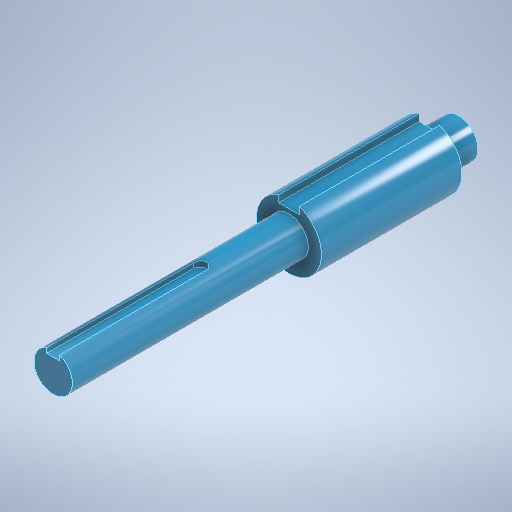
# Autodesk Inventor part: Output Shaft
Saved by Autodesk Inventor 2025 (Build 290162000, 162)
## iProperties
Created: 2024-05-11
Part Number: Output Shaft
Material: Generic
Document SubType Name: Modeling
Designer: BenFr
Density: 1 g/cm^3
Appearance: Sky Blue Dark
Author: BenFr
Autodesk Inventor part; units mm, degrees
ref_plane "YZ Plane" through (0, 0, 0) normal (1, 0, 0) x (0, 1, 0)
ref_plane "XZ Plane" through (0, 0, 0) normal (0, 1, 0) x (-1, 0, 0)
ref_plane "XY Plane" through (0, 0, 0) normal (0, 0, 1) x (1, 0, 0)
sketch "Sketch1" plane through (0, 0, 0) normal (0, 1, 0) x (-1, 0, 0)
  line L0 (0, 0) -> (0, -159.1)
  line L1 (0, 0) -> (7.5, 0)
  line L2 (7.5, 0) -> (7.5, -92.5)
  line L3 (7.5, -92.5) -> (12.7, -92.5)
  line L4 (12.7, -92.5) -> (12.7, -147.6)
  line L5 (12.7, -147.6) -> (7.5, -147.6)
  line L6 (7.5, -147.6) -> (7.5, -159.1)
  line L7 (7.5, -159.1) -> (0, -159.1)
  dimension "d0" = 159.1
  dimension "d1" = 7.5
  dimension "d2" = 92.5
  dimension "d3" = 5.2
  dimension "d4" = 55.1
  constraints: 16 end point, 5 perpendicular, 2 horizontal, 1 vertical
  measures "d0" distance of L0.start L0.end
  measures "d1" distance of L0.start L1.end
  measures "d2" distance of L1.end L2.end
  measures "d3" distance of L2.end L3.end
  measures "d4" distance of L3.end L4.end
revolve "Revolution1" add sketch "Sketch1" angle 360 about axis through (0, 0, 0) along (0, 0, -1)
sketch "Sketch2" plane through (0, 0, 0) normal (0, 0, 1) x (1, 0, 0)
  line L0 (-2.5, 5.15) -> (2.5, 5.15)
  line L1 (2.5, 5.15) -> (2.5, 9.85)
  line L2 (2.5, 9.85) -> (-2.5, 9.85)
  line L3 (-2.5, 9.85) -> (-2.5, 5.15)
  circle A0 centre (0, 0) radius 7.5 projected
  line L4 (-2.5, 5.15) -> (2.5, 9.85) construction
  line L5 (2.5, 5.15) -> (-2.5, 9.85) construction
  line L6 (4, 16.1) -> (-4, 16.1)
  line L7 (-4, 16.1) -> (-4, 9.3)
  line L8 (-4, 9.3) -> (4, 9.3)
  line L9 (4, 9.3) -> (4, 16.1)
  circle A1 centre (0, 0) radius 12.7 projected
  line L10 (4, 16.1) -> (-4, 9.3) construction
  line L11 (-4, 16.1) -> (4, 9.3) construction
  point P0 (0, 7.5)
  point P1 (0, 12.7)
  dimension "d6" = 5
  dimension "d7" = 4.7
  dimension "d8" = 8
  dimension "d9" = 6.8
  constraints: 24 end point, 4 midpoint, 4 parallel, 2 horizontal, 2 perpendicular, 2 vertical alignment, 2 other
  measures "d6" distance of L2.end L1.end
  measures "d7" distance of L1.end L0.end
  measures "d8" distance of L8.end L7.end
  measures "d9" distance of L7.end L6.end
extrude "Extrusion1" cut sketch "Sketch2" against normal blind 60 contours L3 A0 L1 L0 | L3 L8 L1 A0 | L3 L2 L1 L8 picked at (-0.2826, 5.9173)
sketch "Sketch3" plane through (0, 0, -92.5) normal (0, 0, 1) x (1, 0, 0)
  line L0 (-4, 9.3) -> (4, 9.3)
  line L1 (4, 9.3) -> (4, 16.1)
  line L2 (4, 16.1) -> (-4, 16.1)
  line L3 (-4, 16.1) -> (-4, 9.3)
  circle A0 centre (0, 0) radius 12.7 projected
  line L4 (-4, 9.3) -> (4, 16.1) construction
  line L5 (4, 9.3) -> (-4, 16.1) construction
  point P0 (0, 12.7)
  point P1 (4, 12.0536)
  point P2 (-4, 12.0536)
  dimension "d12" = 8
  dimension "d13" = 6.8
  constraints: 12 end point, 2 midpoint, 2 parallel, 1 horizontal, 1 perpendicular, 2 other
  measures "d12" distance of L2.end L1.end
  measures "d13" distance of L1.end L0.end
extrude "Extrusion2" cut sketch "Sketch3" against normal through all contours L3 A0 L1 L0 picked at (0.4513, 10.4092)
fillet "Fillet1" radius 2.5 2 edges at (-2.5, 6.1105, -60) (2.5, 6.1105, -60)
body "Solid1"
